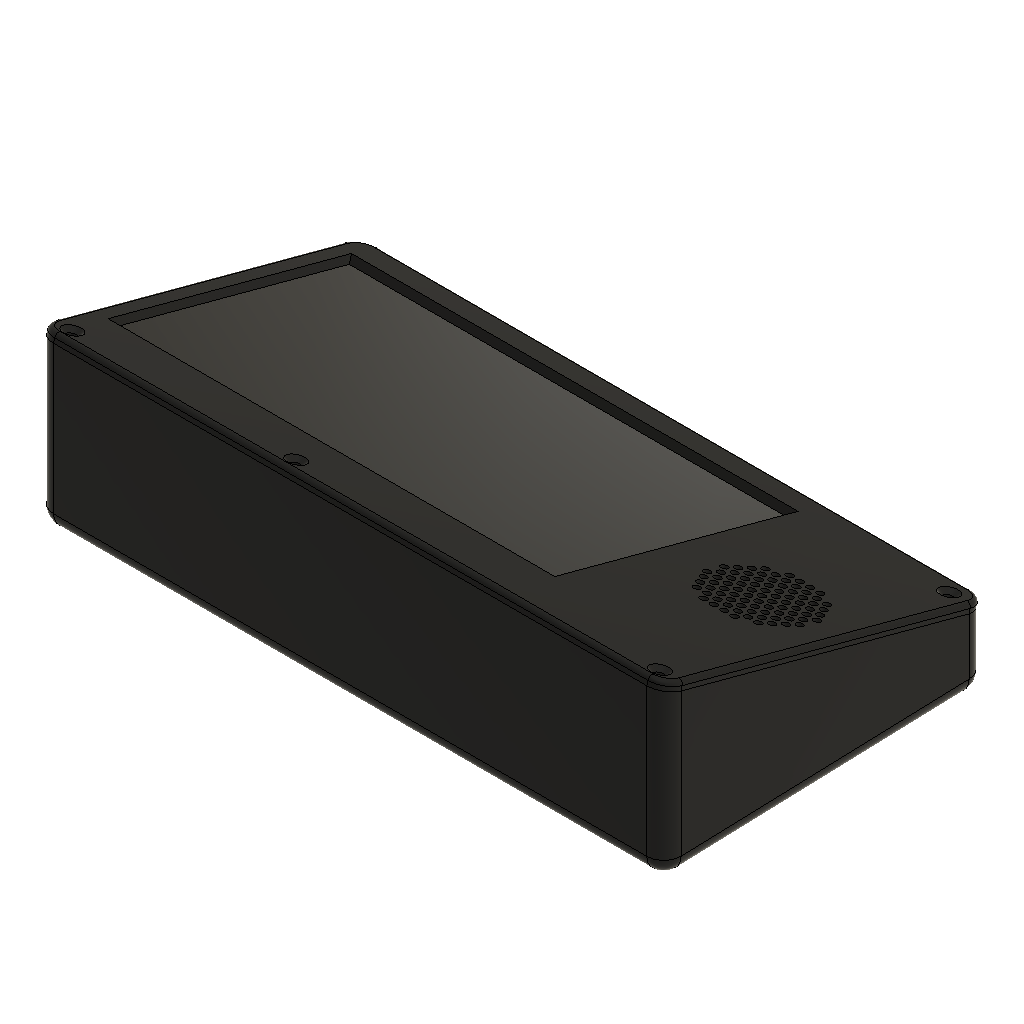
RadioCase (Autodesk Fusion 360 design; units mm, degrees)
part number: 2026-10-21-10-10-32-338
Autodesk Fusion 360 part; units mm, degrees
sketch "Sketch1" plane through (0, 0, 0) normal (1, 0, 0) x (0, 0, -1)
  line L0 (0, 0) -> (0, 117)
  line L1 (0, 117) -> (23.1822, 123.2117)
  line L2 (23.1822, 123.2117) -> (56.0237, 15.0115)
  line L3 (56.0237, 15.0115) -> (0, 0)
extrude "Extrude1" add sketch "Sketch1" along normal blind 220 makes body 1
fillet "Fillet1" radius 6 8 edges at (0, 7.5058, -28.0118) (110, 15.0115, -56.0237) (220, 7.5058, -28.0118) (0, 120.1058, -11.5911) (220, 120.1058, -11.5911) (110, 123.2117, -23.1822) (0, 69.1116, -39.603) (220, 69.1116, -39.603) on bodies 1
extrude "Extrude2" add 1 faces at (144.6667, 39, 0) along direction (0, 0, 1) blind 3 separate body on bodies 1 makes body 2
ref_plane "WorkPlane1" through (0, 0, -61.0237) normal (0, 0, 1) x (1, 0, 0)
sketch "Sketch2" plane through (0, 0, -61.0237) normal (0, 0, 1) x (1, 0, 0)
  circle A0 centre (40.5, 36) radius 4.5
extrude "Extrude3" add sketch "Sketch2" along normal blind 44.7237 separate body makes body 3
ref_plane "WorkPlane2" through (0, 0, -16.3) normal (0, 0, 1) x (1, 0, 0)
sketch "Sketch3" plane through (0, 0, -16.3) normal (0, 0, 1) x (1, 0, 0)
  circle A0 centre (40.5, 36) radius 3.5
extrude "Extrude4" add sketch "Sketch3" along normal blind 6 bodies 3
ref_plane "WorkPlane3" through (0, 0, -61.0237) normal (0, 0, 1) x (1, 0, 0)
sketch "Sketch4" plane through (0, 0, -61.0237) normal (0, 0, 1) x (1, 0, 0)
  circle A0 centre (40.5, 88) radius 4.5
extrude "Extrude5" add sketch "Sketch4" along normal blind 44.7237 separate body makes body 4
ref_plane "WorkPlane4" through (0, 0, -16.3) normal (0, 0, 1) x (1, 0, 0)
sketch "Sketch5" plane through (0, 0, -16.3) normal (0, 0, 1) x (1, 0, 0)
  circle A0 centre (40.5, 88) radius 3.5
extrude "Extrude6" add sketch "Sketch5" along normal blind 6 bodies 4
ref_plane "WorkPlane5" through (0, 0, -61.0237) normal (0, 0, 1) x (1, 0, 0)
sketch "Sketch6" plane through (0, 0, -61.0237) normal (0, 0, 1) x (1, 0, 0)
  circle A0 centre (130.5, 36) radius 4.5
extrude "Extrude7" add sketch "Sketch6" along normal blind 44.7237 separate body makes body 5
ref_plane "WorkPlane6" through (0, 0, -16.3) normal (0, 0, 1) x (1, 0, 0)
sketch "Sketch7" plane through (0, 0, -16.3) normal (0, 0, 1) x (1, 0, 0)
  circle A0 centre (130.5, 36) radius 3.5
extrude "Extrude8" add sketch "Sketch7" along normal blind 6 bodies 5
ref_plane "WorkPlane7" through (0, 0, -61.0237) normal (0, 0, 1) x (1, 0, 0)
sketch "Sketch8" plane through (0, 0, -61.0237) normal (0, 0, 1) x (1, 0, 0)
  circle A0 centre (130.5, 88) radius 4.5
extrude "Extrude9" add sketch "Sketch8" along normal blind 44.7237 separate body makes body 6
ref_plane "WorkPlane8" through (0, 0, -16.3) normal (0, 0, 1) x (1, 0, 0)
sketch "Sketch9" plane through (0, 0, -16.3) normal (0, 0, 1) x (1, 0, 0)
  circle A0 centre (130.5, 88) radius 3.5
extrude "Extrude10" add sketch "Sketch9" along normal blind 6 bodies 6
ref_plane "WorkPlane9" through (0, 0, -61.0237) normal (0, 0, 1) x (1, 0, 0)
sketch "Sketch10" plane through (0, 0, -61.0237) normal (0, 0, 1) x (1, 0, 0)
  circle A0 centre (7, 5) radius 3.5
extrude "Extrude11" add sketch "Sketch10" along normal blind 61.0237 separate body makes body 7
ref_plane "WorkPlane10" through (0, 0, -61.0237) normal (0, 0, 1) x (1, 0, 0)
sketch "Sketch11" plane through (0, 0, -61.0237) normal (0, 0, 1) x (1, 0, 0)
  circle A0 centre (85.5, 5) radius 3.5
extrude "Extrude12" add sketch "Sketch11" along normal blind 61.0237 separate body makes body 8
ref_plane "WorkPlane11" through (0, 0, -61.0237) normal (0, 0, 1) x (1, 0, 0)
sketch "Sketch12" plane through (0, 0, -61.0237) normal (0, 0, 1) x (1, 0, 0)
  circle A0 centre (213, 5) radius 3.5
extrude "Extrude13" add sketch "Sketch12" along normal blind 61.0237 separate body makes body 9
ref_plane "WorkPlane12" through (0, 0, -61.0237) normal (0, 0, 1) x (1, 0, 0)
sketch "Sketch13" plane through (0, 0, -61.0237) normal (0, 0, 1) x (1, 0, 0)
  circle A0 centre (213, 110) radius 3.5
extrude "Extrude14" add sketch "Sketch13" along normal blind 61.0237 separate body makes body 10
combine "Combine1" operation intersect target body 3 tool bodies 1 keep tools
combine "Combine2" operation intersect target body 4 tool bodies 1 keep tools
combine "Combine3" operation intersect target body 5 tool bodies 1 keep tools
combine "Combine4" operation intersect target body 6 tool bodies 1 keep tools
combine "Combine5" operation intersect target body 7 tool bodies 1 keep tools
combine "Combine6" operation intersect target body 8 tool bodies 1 keep tools
combine "Combine7" operation intersect target body 9 tool bodies 1 keep tools
combine "Combine8" operation intersect target body 10 tool bodies 1 keep tools
shell "Shell1" thickness 2.5 removed faces 1 at (144.6667, 39, 0) on bodies 1
combine "Combine9" operation add target body 1 tool bodies 3 4 5 6 7 8 9 10
ref_plane "WorkPlane13" through (0, 0, -66.0237) normal (0, 0, 1) x (1, 0, 0)
sketch "Sketch14" plane through (0, 0, -66.0237) normal (0, 0, 1) x (1, 0, 0)
  circle A0 centre (40.5, 36) radius 2.75
extrude "Extrude15" cut sketch "Sketch14" along normal blind 49.7237 bodies 1
ref_plane "WorkPlane14" through (0, 0, -16.8) normal (0, 0, 1) x (1, 0, 0)
sketch "Sketch15" plane through (0, 0, -16.8) normal (0, 0, 1) x (1, 0, 0)
  circle A0 centre (40.5, 36) radius 1.2
extrude "Extrude16" cut sketch "Sketch15" along normal blind 7 bodies 1
ref_plane "WorkPlane15" through (0, 0, -66.0237) normal (0, 0, 1) x (1, 0, 0)
sketch "Sketch16" plane through (0, 0, -66.0237) normal (0, 0, 1) x (1, 0, 0)
  circle A0 centre (40.5, 88) radius 2.75
extrude "Extrude17" cut sketch "Sketch16" along normal blind 49.7237 bodies 1
ref_plane "WorkPlane16" through (0, 0, -16.8) normal (0, 0, 1) x (1, 0, 0)
sketch "Sketch17" plane through (0, 0, -16.8) normal (0, 0, 1) x (1, 0, 0)
  circle A0 centre (40.5, 88) radius 1.2
extrude "Extrude18" cut sketch "Sketch17" along normal blind 7 bodies 1
ref_plane "WorkPlane17" through (0, 0, -66.0237) normal (0, 0, 1) x (1, 0, 0)
sketch "Sketch18" plane through (0, 0, -66.0237) normal (0, 0, 1) x (1, 0, 0)
  circle A0 centre (130.5, 36) radius 2.75
extrude "Extrude19" cut sketch "Sketch18" along normal blind 49.7237 bodies 1
ref_plane "WorkPlane18" through (0, 0, -16.8) normal (0, 0, 1) x (1, 0, 0)
sketch "Sketch19" plane through (0, 0, -16.8) normal (0, 0, 1) x (1, 0, 0)
  circle A0 centre (130.5, 36) radius 1.2
extrude "Extrude20" cut sketch "Sketch19" along normal blind 7 bodies 1
ref_plane "WorkPlane19" through (0, 0, -66.0237) normal (0, 0, 1) x (1, 0, 0)
sketch "Sketch20" plane through (0, 0, -66.0237) normal (0, 0, 1) x (1, 0, 0)
  circle A0 centre (130.5, 88) radius 2.75
extrude "Extrude21" cut sketch "Sketch20" along normal blind 49.7237 bodies 1
ref_plane "WorkPlane20" through (0, 0, -16.8) normal (0, 0, 1) x (1, 0, 0)
sketch "Sketch21" plane through (0, 0, -16.8) normal (0, 0, 1) x (1, 0, 0)
  circle A0 centre (130.5, 88) radius 1.2
extrude "Extrude22" cut sketch "Sketch21" along normal blind 7 bodies 1
ref_plane "WorkPlane21" through (0, 0, -12) normal (0, 0, 1) x (1, 0, 0)
sketch "Sketch22" plane through (0, 0, -12) normal (0, 0, 1) x (1, 0, 0)
  circle A0 centre (7, 5) radius 1.25
extrude "Extrude23" cut sketch "Sketch22" along normal blind 12.5 bodies 1
ref_plane "WorkPlane22" through (0, 0, -12) normal (0, 0, 1) x (1, 0, 0)
sketch "Sketch23" plane through (0, 0, -12) normal (0, 0, 1) x (1, 0, 0)
  circle A0 centre (85.5, 5) radius 1.25
extrude "Extrude24" cut sketch "Sketch23" along normal blind 12.5 bodies 1
ref_plane "WorkPlane23" through (0, 0, -12) normal (0, 0, 1) x (1, 0, 0)
sketch "Sketch24" plane through (0, 0, -12) normal (0, 0, 1) x (1, 0, 0)
  circle A0 centre (213, 5) radius 1.25
extrude "Extrude25" cut sketch "Sketch24" along normal blind 12.5 bodies 1
ref_plane "WorkPlane24" through (0, 0, -12) normal (0, 0, 1) x (1, 0, 0)
sketch "Sketch25" plane through (0, 0, -12) normal (0, 0, 1) x (1, 0, 0)
  circle A0 centre (213, 110) radius 1.25
extrude "Extrude26" cut sketch "Sketch25" along normal blind 12.5 bodies 1
ref_plane "WorkPlane25" through (-1, 0, 0) normal (1, 0, 0) x (0, 1, 0)
sketch "Sketch26" plane through (-1, 0, 0) normal (1, 0, 0) x (0, 0, -1)
  line L0 (12.9, 42) -> (12.9, 90)
  line L1 (4.9, 42) -> (4.9, 90)
  arc A0 (12.9, 90) -> (4.9, 90) centre (8.9, 90) ccw
  arc A1 (4.9, 42) -> (12.9, 42) centre (8.9, 42) ccw
extrude "Extrude27" cut sketch "Sketch26" along normal blind 4.1 bodies 1
ref_plane "WorkPlane26" through (0, 0, -10.2) normal (0, 0, 1) x (1, 0, 0)
sketch "Sketch27" plane through (0, 0, -10.2) normal (0, 0, 1) x (1, 0, 0)
  line L0 (56.3, 112) -> (72.7, 112)
  line L1 (72.7, 112) -> (72.7, 137)
  line L2 (72.7, 137) -> (56.3, 137)
  line L3 (56.3, 137) -> (56.3, 112)
extrude "Extrude28" cut sketch "Sketch27" along normal blind 4 bodies 1
ref_plane "WorkPlane27" through (0, 0, -13) normal (0, 0, 1) x (1, 0, 0)
sketch "Sketch28" plane through (0, 0, -13) normal (0, 0, 1) x (1, 0, 0)
  line L0 (54.5, 124.5) -> (54.5, 127)
  line L1 (74.5, 124.5) -> (74.5, 127)
  arc A0 (74.5, 127) -> (54.5, 127) centre (64.5, 127) ccw
  arc A1 (54.5, 124.5) -> (74.5, 124.5) centre (64.5, 124.5) ccw
extrude "Extrude29" cut sketch "Sketch28" along normal blind 13.1 bodies 1
fillet "Fillet2" radius 1.5 64 edges at (1.7574, 1.8194, 3) (110, 0, 3) (218.2426, 1.8194, 3) (220, 58.5, 3) (218.2426, 115.1806, 3) (110, 117, 3) (1.7574, 115.1806, 3) (0, 58.5, 3) (110, 0, 3) (218.2426, 1.8194, 3) (220, 58.5, 3) (218.2426, 115.1806, 3) (110, 117, 3) (1.7574, 115.1806, 3) (0, 58.5, 3) (1.7574, 1.8194, 3) (218.2426, 1.8194, 3) (220, 58.5, 3) (218.2426, 115.1806, 3) (110, 117, 3) (1.7574, 115.1806, 3) (0, 58.5, 3) (1.7574, 1.8194, 3) (110, 0, 3) (220, 58.5, 3) (218.2426, 115.1806, 3) (110, 117, 3) (1.7574, 115.1806, 3) (0, 58.5, 3) (1.7574, 1.8194, 3) (110, 0, 3) (218.2426, 1.8194, 3) (218.2426, 115.1806, 3) (110, 117, 3) (1.7574, 115.1806, 3) (0, 58.5, 3) (1.7574, 1.8194, 3) (110, 0, 3) (218.2426, 1.8194, 3) (220, 58.5, 3) (110, 117, 3) (1.7574, 115.1806, 3) (0, 58.5, 3) (1.7574, 1.8194, 3) (110, 0, 3) (218.2426, 1.8194, 3) (220, 58.5, 3) (218.2426, 115.1806, 3) (1.7574, 115.1806, 3) (0, 58.5, 3) (1.7574, 1.8194, 3) (110, 0, 3) (218.2426, 1.8194, 3) (220, 58.5, 3) (218.2426, 115.1806, 3) (110, 117, 3) (0, 58.5, 3) (1.7574, 1.8194, 3) (110, 0, 3) (218.2426, 1.8194, 3) (220, 58.5, 3) (218.2426, 115.1806, 3) (110, 117, 3) (1.7574, 115.1806, 3) on bodies 2
ref_plane "WorkPlane28" through (0, 0, -1) normal (0, 0, 1) x (1, 0, 0)
sketch "Sketch29" plane through (0, 0, -1) normal (0, 0, 1) x (1, 0, 0)
  line L0 (6.1, 18.9) -> (162.71, 18.9)
  line L1 (162.71, 18.9) -> (162.71, 107.22)
  line L2 (162.71, 107.22) -> (6.1, 107.22)
  line L3 (6.1, 107.22) -> (6.1, 18.9)
extrude "Extrude30" cut sketch "Sketch29" along normal blind 5 bodies 2
ref_plane "WorkPlane29" through (0, 0, -1) normal (0, 0, 1) x (1, 0, 0)
sketch "Sketch30" plane through (0, 0, -1) normal (0, 0, 1) x (1, 0, 0)
  circle A0 centre (188.35, 46.4115) radius 1.2
  circle A1 centre (191.95, 46.4115) radius 1.2
  circle A2 centre (195.55, 46.4115) radius 1.2
  circle A3 centre (199.15, 46.4115) radius 1.2
  circle A4 centre (182.95, 49.5292) radius 1.2
  circle A5 centre (186.55, 49.5292) radius 1.2
  circle A6 centre (190.15, 49.5292) radius 1.2
  circle A7 centre (193.75, 49.5292) radius 1.2
  circle A8 centre (197.35, 49.5292) radius 1.2
  circle A9 centre (200.95, 49.5292) radius 1.2
  circle A10 centre (204.55, 49.5292) radius 1.2
  circle A11 centre (181.15, 52.6469) radius 1.2
  circle A12 centre (184.75, 52.6469) radius 1.2
  circle A13 centre (188.35, 52.6469) radius 1.2
  circle A14 centre (191.95, 52.6469) radius 1.2
  circle A15 centre (195.55, 52.6469) radius 1.2
  circle A16 centre (199.15, 52.6469) radius 1.2
  circle A17 centre (202.75, 52.6469) radius 1.2
  circle A18 centre (206.35, 52.6469) radius 1.2
  circle A19 centre (179.35, 55.7646) radius 1.2
  circle A20 centre (182.95, 55.7646) radius 1.2
  circle A21 centre (186.55, 55.7646) radius 1.2
  circle A22 centre (190.15, 55.7646) radius 1.2
  circle A23 centre (193.75, 55.7646) radius 1.2
  circle A24 centre (197.35, 55.7646) radius 1.2
  circle A25 centre (200.95, 55.7646) radius 1.2
  circle A26 centre (204.55, 55.7646) radius 1.2
  circle A27 centre (208.15, 55.7646) radius 1.2
  circle A28 centre (177.55, 58.8823) radius 1.2
  circle A29 centre (181.15, 58.8823) radius 1.2
  circle A30 centre (184.75, 58.8823) radius 1.2
  circle A31 centre (188.35, 58.8823) radius 1.2
  circle A32 centre (191.95, 58.8823) radius 1.2
  circle A33 centre (195.55, 58.8823) radius 1.2
  circle A34 centre (199.15, 58.8823) radius 1.2
  circle A35 centre (202.75, 58.8823) radius 1.2
  circle A36 centre (206.35, 58.8823) radius 1.2
  circle A37 centre (209.95, 58.8823) radius 1.2
  circle A38 centre (179.35, 62) radius 1.2
  circle A39 centre (182.95, 62) radius 1.2
  circle A40 centre (186.55, 62) radius 1.2
  circle A41 centre (190.15, 62) radius 1.2
  circle A42 centre (193.75, 62) radius 1.2
  circle A43 centre (197.35, 62) radius 1.2
  circle A44 centre (200.95, 62) radius 1.2
  circle A45 centre (204.55, 62) radius 1.2
  circle A46 centre (208.15, 62) radius 1.2
  circle A47 centre (177.55, 65.1177) radius 1.2
  circle A48 centre (181.15, 65.1177) radius 1.2
  circle A49 centre (184.75, 65.1177) radius 1.2
  circle A50 centre (188.35, 65.1177) radius 1.2
  circle A51 centre (191.95, 65.1177) radius 1.2
  circle A52 centre (195.55, 65.1177) radius 1.2
  circle A53 centre (199.15, 65.1177) radius 1.2
  circle A54 centre (202.75, 65.1177) radius 1.2
  circle A55 centre (206.35, 65.1177) radius 1.2
  circle A56 centre (209.95, 65.1177) radius 1.2
  circle A57 centre (179.35, 68.2354) radius 1.2
  circle A58 centre (182.95, 68.2354) radius 1.2
  circle A59 centre (186.55, 68.2354) radius 1.2
  circle A60 centre (190.15, 68.2354) radius 1.2
  circle A61 centre (193.75, 68.2354) radius 1.2
  circle A62 centre (197.35, 68.2354) radius 1.2
  circle A63 centre (200.95, 68.2354) radius 1.2
  circle A64 centre (204.55, 68.2354) radius 1.2
  circle A65 centre (208.15, 68.2354) radius 1.2
  circle A66 centre (181.15, 71.3531) radius 1.2
  circle A67 centre (184.75, 71.3531) radius 1.2
  circle A68 centre (188.35, 71.3531) radius 1.2
  circle A69 centre (191.95, 71.3531) radius 1.2
  circle A70 centre (195.55, 71.3531) radius 1.2
  circle A71 centre (199.15, 71.3531) radius 1.2
  circle A72 centre (202.75, 71.3531) radius 1.2
  circle A73 centre (206.35, 71.3531) radius 1.2
  circle A74 centre (182.95, 74.4708) radius 1.2
  circle A75 centre (186.55, 74.4708) radius 1.2
  circle A76 centre (190.15, 74.4708) radius 1.2
  circle A77 centre (193.75, 74.4708) radius 1.2
  circle A78 centre (197.35, 74.4708) radius 1.2
  circle A79 centre (200.95, 74.4708) radius 1.2
  circle A80 centre (204.55, 74.4708) radius 1.2
  circle A81 centre (188.35, 77.5885) radius 1.2
  circle A82 centre (191.95, 77.5885) radius 1.2
  circle A83 centre (195.55, 77.5885) radius 1.2
  circle A84 centre (199.15, 77.5885) radius 1.2
extrude "Extrude31" cut sketch "Sketch30" along normal blind 5 bodies 2
ref_plane "WorkPlane30" through (0, 0, -5.6) normal (0, 0, 1) x (1, 0, 0)
sketch "Sketch31" plane through (0, 0, -5.6) normal (0, 0, 1) x (1, 0, 0)
  circle A0 centre (193.75, 62) radius 22.4
  circle A1 centre (193.75, 62) radius 20.4
extrude "Extrude32" add sketch "Sketch31" along normal blind 5.6 bodies 2
ref_plane "WorkPlane31" through (0, 0, -1) normal (0, 0, 1) x (1, 0, 0)
sketch "Sketch32" plane through (0, 0, -1) normal (0, 0, 1) x (1, 0, 0)
  circle A0 centre (7, 5) radius 1.7
extrude "Extrude33" cut sketch "Sketch32" along normal blind 5 bodies 2
ref_plane "WorkPlane32" through (0, 0, 3) normal (0, 0, 1) x (1, 0, 0)
sketch "Sketch33" plane through (0, 0, 3) normal (0, 0, 1) x (1, 0, 0)
  circle A0 centre (7, 5) radius 3.2
extrude "Extrude34" cut sketch "Sketch33" against normal blind 1.5 draft -45 bodies 2
ref_plane "WorkPlane33" through (0, 0, -1) normal (0, 0, 1) x (1, 0, 0)
sketch "Sketch34" plane through (0, 0, -1) normal (0, 0, 1) x (1, 0, 0)
  circle A0 centre (85.5, 5) radius 1.7
extrude "Extrude35" cut sketch "Sketch34" along normal blind 5 bodies 2
ref_plane "WorkPlane34" through (0, 0, 3) normal (0, 0, 1) x (1, 0, 0)
sketch "Sketch35" plane through (0, 0, 3) normal (0, 0, 1) x (1, 0, 0)
  circle A0 centre (85.5, 5) radius 3.2
extrude "Extrude36" cut sketch "Sketch35" against normal blind 1.5 draft -45 bodies 2
ref_plane "WorkPlane35" through (0, 0, -1) normal (0, 0, 1) x (1, 0, 0)
sketch "Sketch36" plane through (0, 0, -1) normal (0, 0, 1) x (1, 0, 0)
  circle A0 centre (213, 5) radius 1.7
extrude "Extrude37" cut sketch "Sketch36" along normal blind 5 bodies 2
ref_plane "WorkPlane36" through (0, 0, 3) normal (0, 0, 1) x (1, 0, 0)
sketch "Sketch37" plane through (0, 0, 3) normal (0, 0, 1) x (1, 0, 0)
  circle A0 centre (213, 5) radius 3.2
extrude "Extrude38" cut sketch "Sketch37" against normal blind 1.5 draft -45 bodies 2
ref_plane "WorkPlane37" through (0, 0, -1) normal (0, 0, 1) x (1, 0, 0)
sketch "Sketch38" plane through (0, 0, -1) normal (0, 0, 1) x (1, 0, 0)
  circle A0 centre (213, 110) radius 1.7
extrude "Extrude39" cut sketch "Sketch38" along normal blind 5 bodies 2
ref_plane "WorkPlane38" through (0, 0, 3) normal (0, 0, 1) x (1, 0, 0)
sketch "Sketch39" plane through (0, 0, 3) normal (0, 0, 1) x (1, 0, 0)
  circle A0 centre (213, 110) radius 3.2
extrude "Extrude40" cut sketch "Sketch39" against normal blind 1.5 draft -45 bodies 2
ref_plane "WorkPlane39" through (0, 0, -5) normal (0, 0, 1) x (1, 0, 0)
sketch "Sketch40" plane through (0, 0, -5) normal (0, 0, 1) x (1, 0, 0)
  circle A0 centre (193.75, 62) radius 20
extrude "Extrude41" add sketch "Sketch40" along normal blind 5 separate body makes body 11
ref_plane "WorkPlane40" through (0, 0, -5.7) normal (0, 0, 1) x (1, 0, 0)
sketch "Sketch41" plane through (0, 0, -5.7) normal (0, 0, 1) x (1, 0, 0)
  line L0 (3, 11.85) -> (168, 11.85)
  line L1 (168, 11.85) -> (168, 112.15)
  line L2 (168, 112.15) -> (3, 112.15)
  line L3 (3, 112.15) -> (3, 11.85)
extrude "Extrude42" add sketch "Sketch41" along normal blind 5.4 separate body makes body 12
ref_plane "WorkPlane41" through (0, 0, -7.3) normal (0, 0, 1) x (1, 0, 0)
sketch "Sketch42" plane through (0, 0, -7.3) normal (0, 0, 1) x (1, 0, 0)
  line L0 (3, 10) -> (168, 10)
  line L1 (168, 10) -> (168, 114)
  line L2 (168, 114) -> (3, 114)
  line L3 (3, 114) -> (3, 10)
extrude "Extrude43" add sketch "Sketch42" along normal blind 1.6 separate body makes body 13
ref_plane "WorkPlane42" through (0, 0, -10.3) normal (0, 0, 1) x (1, 0, 0)
sketch "Sketch43" plane through (0, 0, -10.3) normal (0, 0, 1) x (1, 0, 0)
  circle A0 centre (40.5, 36) radius 1.75
extrude "Extrude44" add sketch "Sketch43" along normal blind 3 separate body makes body 14
ref_plane "WorkPlane43" through (0, 0, -10.3) normal (0, 0, 1) x (1, 0, 0)
sketch "Sketch44" plane through (0, 0, -10.3) normal (0, 0, 1) x (1, 0, 0)
  circle A0 centre (40.5, 88) radius 1.75
extrude "Extrude45" add sketch "Sketch44" along normal blind 3 separate body makes body 15
ref_plane "WorkPlane44" through (0, 0, -10.3) normal (0, 0, 1) x (1, 0, 0)
sketch "Sketch45" plane through (0, 0, -10.3) normal (0, 0, 1) x (1, 0, 0)
  circle A0 centre (130.5, 36) radius 1.75
extrude "Extrude46" add sketch "Sketch45" along normal blind 3 separate body makes body 16
ref_plane "WorkPlane45" through (0, 0, -10.3) normal (0, 0, 1) x (1, 0, 0)
sketch "Sketch46" plane through (0, 0, -10.3) normal (0, 0, 1) x (1, 0, 0)
  circle A0 centre (130.5, 88) radius 1.75
extrude "Extrude47" add sketch "Sketch46" along normal blind 3 separate body makes body 17
move_body "Move1" bodies 1 2 11 12 13 14 15 16 17 to x (1, 0, 0) y (0, 0.965926, -0.258819) z (0, 0.258819, 0.965926) at (0, 0, 0)
equation "d136 = -( 1.50 mm )"
equation "d144 = -( 1.50 mm )"
equation "d152 = -( 1.50 mm )"
equation "d160 = -( 1.50 mm )"
named bodies: "Body", "FrontPanel", "Speaker_REF", "Glass", "PCB", "Standoff_REF", "Standoff_REF (1)", "Standoff_REF (2)", "Standoff_REF (3)"
